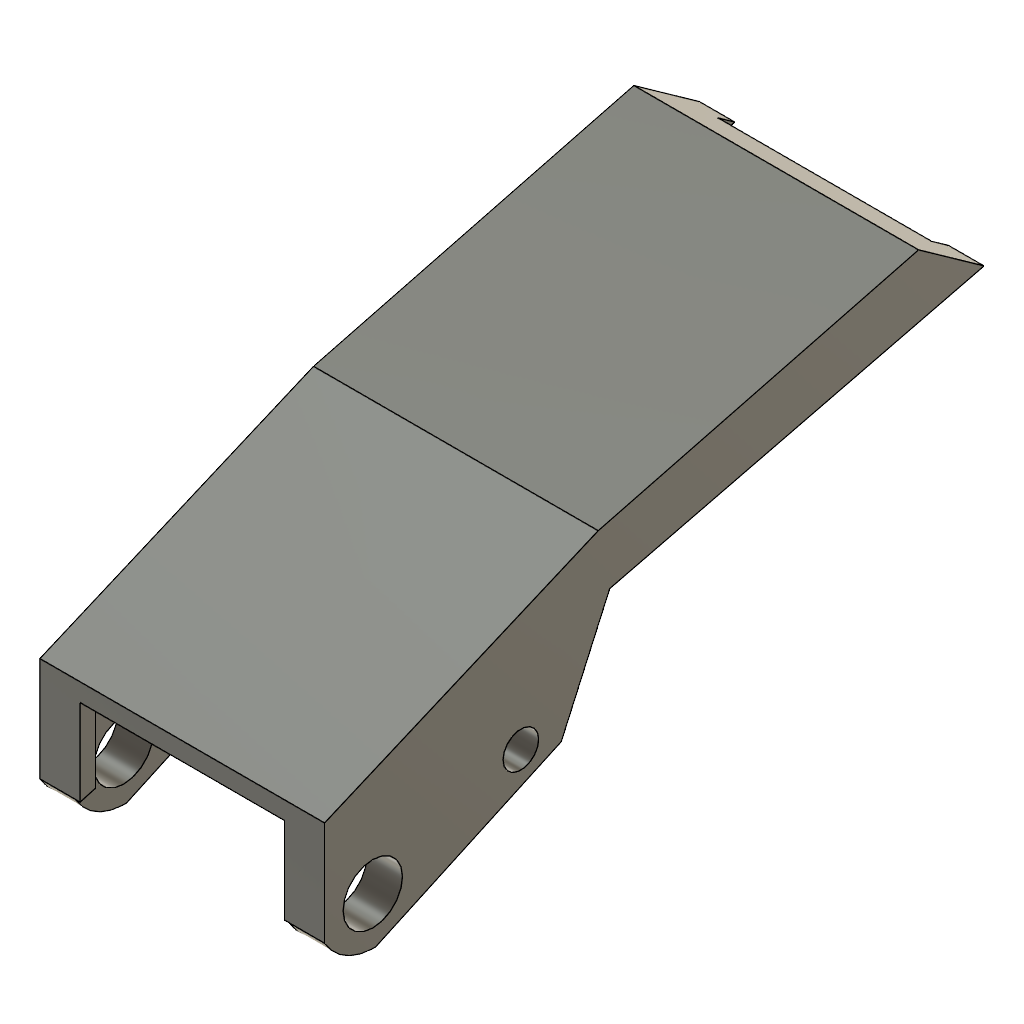
triggertop (Autodesk Fusion 360 design; units mm, degrees)
Autodesk Fusion 360 part; units mm, degrees
sketch "Sketch1" plane through (0, 0, 0) normal (1, 0, 0) x (0, 1, 0)
  line L0 (-0.0636, 2.4163) -> (-0.0636, 11.2)
  arc A0 (-0.0636, 2.4163) -> (4.2508, 0) centre (4.0754, 4.7468) ccw
  line L1 (1.75, 0) -> (22.5, 0)
  line L2 (4.2508, 0) -> (19.8905, 7.1582)
  line L3 (19.8905, 7.1582) -> (23.973, 16.2869)
  line L4 (23.973, 16.2869) -> (55.5289, 24.0634)
  line L5 (-0.0636, 11.2) -> (23, 21)
  line L6 (23, 21) -> (50, 28)
  line L7 (50, 28) -> (55.5289, 24.0634)
  line L8 (49.7397, 26.5895) -> (52.4669, 24.6477)
  line L9 (23.0455, 17.3972) -> (52.4669, 24.6477)
  line L10 (18.9038, 8.1363) -> (23.0455, 17.3972)
  line L11 (3.9643, 1.2986) -> (18.9038, 8.1363)
  arc A1 (1.2364, 2.7865) -> (3.9643, 1.2986) centre (4.0754, 4.7468) ccw
  line L12 (1.2364, 2.7865) -> (1.2364, 10.3399)
  line L13 (1.2364, 10.3399) -> (23.4196, 19.7658)
  line L14 (23.4196, 19.7658) -> (49.7397, 26.5895)
  line L15 (1.2364, 10.3399) -> (-0.0636, 9.7875)
  line L16 (1.2364, 2.7865) -> (-0.0636, 2.4163)
  line L17 (49.7397, 26.5895) -> (51.3827, 27.0155)
  line L18 (52.4669, 24.6477) -> (54.11, 25.0737)
  dimension "d2" = 4.75
  dimension "d3" = 11.2
  dimension "d4" = 17.2
  dimension "d5" = 10
  dimension "d6" = 32.5
  dimension "d10" = -1.3
  constraint vertical L0
  constraint coincident A0.end L1
  constraint coincident L0 L15.end
  constraint parallel L13 L15
  constraint coincident L7 L17.end
  constraint parallel L14 L17
  constraint coincident L7 L18.end
  constraint parallel L17 L18
  measures "d2" radius of A0
  measures "d3" vertical distance of origin L0.end
  measures "d4" distance of A0.end L2.end
  measures "d5" distance of L2.end L3.end
  measures "d6" distance of L3.end L4.end
extrude "Extrude1" add sketch "Sketch1" along normal mid plane 24
extrude "Extrude4" cut sketch "Sketch1" along normal mid plane 18 contours A0 L2 L3 L4 L7 L9 L10 L11 A1 L16 L18 | L8 L9 L10 L11 A1 L12 L13 L14
sketch "Sketch2" plane through (0, -0.0636, 0) normal (0, -1, 0) x (1, 0, 0)
  line L0 (9, 2.4163) -> (12, 2.4163)
  line L1 (12, 2.4163) -> (12, 11.2)
  line L2 (12, 11.2) -> (-12, 11.2)
  line L3 (-12, 11.2) -> (-12, 2.4163)
  line L4 (-12, 2.4163) -> (-9, 2.4163)
  line L5 (-9, 2.4163) -> (9, 2.4163)
  line L6 (-8.6058, 9.6823) -> (-8.6058, 2.4163)
  line L7 (-8.6058, 2.4163) -> (-10.5, 2.4163)
  line L8 (0, 2.4163) -> (0, 11.2)
  line L9 (8.6058, 9.6823) -> (8.6058, 2.4163)
  line L10 (8.6058, 2.4163) -> (10.5, 2.4163)
  line L11 (-8.6058, 9.6823) -> (8.6058, 9.6823)
  line L12 (8.6058, 2.4163) -> (-8.6058, 2.4163)
  constraint midpoint L4 L7.end
  constraint coincident L5 L6.end
  constraint perpendicular L5 L6
  constraint symmetric L7.end L8 L10.end
  constraint symmetric L6.start L8 L9.start
  constraint symmetric L6.end L8 L9.end
extrude "Extrude5" cut sketch "Sketch2" against normal blind 22.5 contours L5 L8 L9 L11 L12 | L5 L6 L8 L11 L12
sketch "Sketch3" plane through (12, 0, 0) normal (1, 0, 0) x (0, 1, 0)
  line L0 (19.8905, 7.1582) -> (23.973, 16.2869)
  line L1 (23.973, 16.2869) -> (55.5289, 24.0634)
  line L2 (55.5289, 24.0634) -> (50, 28)
  line L3 (50, 28) -> (23, 21)
  line L4 (23, 21) -> (-0.0636, 11.2)
  circle A0 centre (4, 4) radius 2.5
  arc A1 (-0.0636, 2.4163) -> (3.9, 0) centre (4.0754, 4.7468) ccw
  line L5 (3.9, 0) -> (4.2508, 0)
  line L6 (4.2508, 0) -> (19.8905, 7.1582)
  line L7 (-0.0636, 11.2) -> (-0.0636, 2.4163)
  dimension "d19" = 5
  measures "d19" diameter of A0
extrude "Extrude6" cut sketch "Sketch3" against normal blind 31 contours A0
sketch "Sketch5" plane through (12, 0, 0) normal (1, 0, 0) x (0, 1, 0)
  circle A0 centre (4, 4) radius 2.5
  arc A1 (-0.0636, 2.4163) -> (3.9, 0) centre (4.0754, 4.7468) ccw
  line L0 (3.9, 0) -> (4.2508, 0)
  line L1 (4.2508, 0) -> (19.8905, 7.1582)
  line L2 (19.8905, 7.1582) -> (23.973, 16.2869)
  line L3 (23.973, 16.2869) -> (55.5289, 24.0634)
  line L4 (55.5289, 24.0634) -> (50, 28)
  line L5 (50, 28) -> (23, 21)
  line L6 (23, 21) -> (-0.0636, 11.2)
  line L7 (-0.0636, 11.2) -> (-0.0636, 2.4163)
  line L8 (4, 4) -> (16.4795, 8.2844) construction
  circle A2 centre (16.4795, 8.2844) radius 1.5
  line L9 (16.4795, 8.2844) -> (17.4964, 6.0625) construction
  dimension "d28" = 3
  constraint coincident A0.centre L8.start
  constraint coincident L8.end A2.centre
  constraint coincident L1 L9.end
  constraint perpendicular L1 L9
  measures "d28" diameter of A2
extrude "Extrude8" cut sketch "Sketch5" against normal blind 34 contours A2
